PCB_spacer_v1 (Autodesk Fusion 360 design; units mm, degrees)
Autodesk Fusion 360 part; units mm, degrees
sketch "Sketch1" plane through (0, 0, 0) normal (0, 0, 1) x (1, 0, 0)
  circle A0 centre (0, 0) radius 3
  circle A1 centre (0, 0) radius 0.95
  circle A2 centre (0, 0) radius 1.15
  dimension "d1" = 6
  dimension "d2" = 1.9
  dimension "d3" = 2.3
  constraint coincident A0.centre A1.centre
  constraint concentric A0 A1
  measures "d1" diameter of A0
  measures "d2" diameter of A1
  measures "d3" diameter of A2
extrude "Extrude1" add sketch "Sketch1" against normal blind 5 contours A0
extrude "Extrude2" add sketch "Sketch1" along normal blind 5 contours A0 | A2
